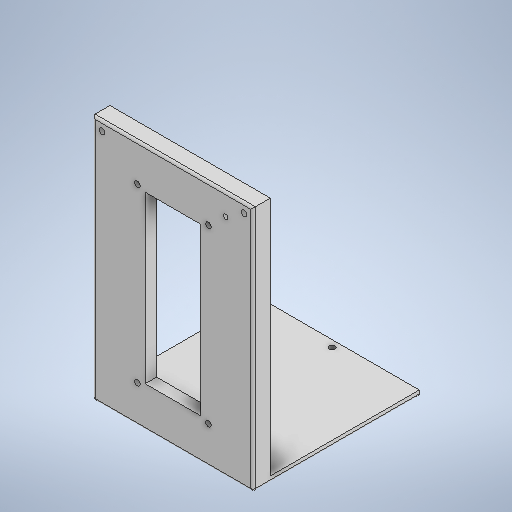
# Autodesk Inventor part: gora
Saved by Autodesk Inventor 2025.2 (Build 292293000, 293)
## iProperties
Created: 2026-10-25
Part Number: gora
Material: Generic
Document SubType Name: Modeling
Designer: Kacper
Density: 1 g/cm^3
Appearance: Default
Author: Kacper
Autodesk Inventor part; units mm, degrees
ref_plane "YZ Plane" through (0, 0, 0) normal (1, 0, 0) x (0, 1, 0)
ref_plane "XZ Plane" through (0, 0, 0) normal (0, 1, 0) x (-1, 0, 0)
ref_plane "XY Plane" through (0, 0, 0) normal (0, 0, 1) x (1, 0, 0)
sketch "Sketch1" plane through (0, 0, 0) normal (0, 0, 1) x (1, 0, 0)
  line L0 (-35, 53.75) -> (35, 53.75)
  line L1 (35, 53.75) -> (35, -53.75)
  line L2 (35, -53.75) -> (-35, -53.75)
  line L3 (-35, -53.75) -> (-35, 53.75)
  line L4 (-35, 53.75) -> (35, -53.75) construction
  line L5 (35, 53.75) -> (-35, -53.75) construction
  point P0 (0, 0)
  dimension "d0" = 70
  dimension "d1" = 107.5
  constraints: 12 end point, 2 midpoint, 2 parallel, 1 horizontal, 1 perpendicular
  measures "d0" distance of L0.start L0.end
  measures "d1" distance of L0.end L1.end
extrude "Extrusion1" add sketch "Sketch1" along normal blind 5
sketch "Sketch6" plane through (0, 0, 0) normal (0, 0, -1) x (-1, 0, 0)
  line L0 (35, -53.75) -> (-35, -53.75) projected
  line L1 (35, 53.75) -> (35, -53.75) projected
  line L2 (-35, 53.75) -> (35, 53.75) projected
  line L3 (-35, -53.75) -> (-35, 53.75) projected
  line L4 (-32.5, 43.442) -> (32.5, 43.442)
  line L5 (32.5, 43.442) -> (32.5, -53.75)
  line L6 (32.5, -53.75) -> (-32.5, -53.75)
  line L7 (-32.5, -53.75) -> (-32.5, 43.442)
  point P0 (0, 0)
  dimension "d47" = 2.5
  dimension "d48" = 2.5
  dimension "d49" = 10.308
  constraints: 8 end point, 2 parallel, 1 horizontal, 1 perpendicular, 1 point on line
  measures "d47" distance between parallel lines of L3 L7
  measures "d48" distance between parallel lines of L1 L5
  measures "d49" distance between parallel lines of L2 L4
extrude "Extrusion3" add sketch "Sketch6" along normal blind 2.5 contours L0 L5 L4 L7 L3 L2 L1
sketch "Sketch7" plane through (0, 0, 5) normal (0, 0, 1) x (1, 0, 0)
  line L0 (-35, -53.75) -> (35, -53.75) projected
  line L1 (35, -53.75) -> (35, 53.75) projected
  line L2 (35, 53.75) -> (-35, 53.75) projected
  line L3 (-35, 53.75) -> (-35, -53.75) projected
  point P0 (0, 0)
  point P1 (-31, 49.75)
  point P2 (31, 49.75)
  dimension "d52" = 4
  dimension "d53" = 4
  dimension "d54" = 4
  dimension "d55" = 4
  measures "d52" distance from line of L2 point (31, 49.75)
  measures "d53" distance from line of point (31, 49.75) L1
  measures "d54" distance from line of L3 point (-31, 49.75)
  measures "d55" distance from line of L2 point (-31, 49.75)
hole "Hole4" at (-31, 49.75, 5) at (31, 49.75, 5) direction (0, 0, -1) diameter 2.459 depth 7.5 thread size "M3x0.5" class "6H" standard "ISO Metric profile"
fillet "Fillet5" radius 1 4 edges at (35, 0, 5) (0, 53.75, 5) (-35, 0, 5) (0, -53.75, 5)
sketch "Sketch8" plane through (0, 0, 0) normal (0, 0, -1) x (-1, 0, 0)
  line L0 (-32.5, 43.442) -> (-32.5, -53.75) projected
  line L1 (32.5, -53.75) -> (-32.5, -53.75) projected
  line L2 (32.5, -53.75) -> (32.5, 43.442) projected
  line L3 (32.5, 43.442) -> (-32.5, 43.442) projected
  line L4 (32.5, -53.75) -> (-32.5, -53.75)
  line L5 (-32.5, -53.75) -> (-32.5, -51.25)
  line L6 (-32.5, -51.25) -> (32.5, -51.25)
  line L7 (32.5, -51.25) -> (32.5, -53.75)
  point P0 (0, 0)
  dimension "d64" = 2.5
  constraints: 8 end point, 2 parallel, 1 horizontal, 1 perpendicular, 1 point on line
  measures "d64" distance between parallel lines of L1 L6
extrude "Extrusion4" add sketch "Sketch8" along normal blind 67.5 contours L6 L2 L1 L0
sketch "Sketch9" plane through (0, 0, -2.5) normal (0, 0, -1) x (-1, 0, 0)
  line L0 (35, -53.75) -> (35, 53.75) projected
  line L1 (32.5, -53.75) -> (35, -53.75) projected
  line L2 (32.5, -53.75) -> (32.5, -51.25) projected
  line L3 (32.5, 43.442) -> (32.5, -51.25) projected
  line L4 (-35, 53.75) -> (-35, -53.75) projected
  line L5 (-35, -53.75) -> (-32.5, -53.75) projected
  line L6 (-32.5, -51.25) -> (-32.5, 43.442) projected
  line L7 (32.5, -51.25) -> (-32.5, -51.25) projected
  line L8 (-32.5, -53.75) -> (32.5, -53.75) projected
  line L9 (-32.5, -51.25) -> (-32.5, -53.75) projected
  line L10 (32.5, -51.25) -> (35, -51.25)
  line L11 (35, -51.25) -> (35, -53.75)
  line L12 (35, -53.75) -> (32.5, -53.75)
  line L13 (32.5, -53.75) -> (32.5, -51.25)
  line L14 (-32.5, -51.25) -> (-35, -51.25)
  line L15 (-35, -51.25) -> (-35, -53.75)
  line L16 (-35, -53.75) -> (-32.5, -53.75)
  line L17 (-32.5, -53.75) -> (-32.5, -51.25)
  point P0 (0, 0)
  constraints: 16 end point, 4 parallel, 2 horizontal, 2 perpendicular
extrude "Extrusion5" add sketch "Sketch9" along normal up to surface (65 mm away) contours L1 L2 L10 L0 | L5 L4 L14 L9
sketch "Sketch11" plane through (-35, -53.75, 4) normal (0, -1, 0) x (1, 0, 0)
  line L0 (0, 0) -> (70, 0) projected
  line L1 (0, 0) -> (0, -71.5) projected
  line L2 (0, -71.5) -> (70, -71.5) projected
  line L3 (70, -71.5) -> (70, 0) projected
  point P0 (35, -4)
  point P1 (35, -68.5)
  dimension "d79" = 3
  dimension "d80" = 35
  measures "d79" distance from line of point (35, -68.5) L2
  measures "d80" distance from line of L3 point (35, -68.5)
hole "Hole6" at (0, -53.75, -64.5) direction (0, 1, 0) diameter 2.459 depth 2.5 thread size "M3x0.5" class "6H" standard "ISO Metric profile"
fillet "Fillet7" radius 1 5 edges at (34.7071, -53.4571, 4.7071) (35, -53.75, -31.75) (-34.7071, -53.4571, 4.7071) (-35, -53.75, -31.75) (0, -53.75, -67.5)
sketch "Sketch12" plane through (0, 0, 5) normal (0, 0, 1) x (1, 0, 0)
  circle A0 centre (-31, 49.75) radius 1.2295 projected
  circle A1 centre (31, 49.75) radius 1.2295 projected
  line L0 (-34, -52.75) -> (-34, 52.75) projected
  line L1 (34, -52.75) -> (-34, -52.75) projected
  line L2 (34, 52.75) -> (34, -52.75) projected
  line L3 (-34, 52.75) -> (34, 52.75) projected
  line L4 (35, -52.75) -> (35, 53.75) projected
  line L5 (-35, 53.75) -> (-35, -52.75) projected
  line L6 (35, 53.75) -> (-35, 53.75) projected
  line L7 (-34, -53.75) -> (34, -53.75) projected
  line L8 (-12.1, 36.2) -> (12.1, 36.2)
  line L9 (12.1, 36.2) -> (12.1, -36.2)
  line L10 (12.1, -36.2) -> (-12.1, -36.2)
  line L11 (-12.1, -36.2) -> (-12.1, 36.2)
  point P0 (0, 0)
  point P1 (-15.5, 37.5)
  point P2 (15.5, 37.5)
  point P3 (-15.5, -37.5)
  point P4 (15.5, -37.5)
  point P5 (0, -36.2)
  point P6 (0, 36.2)
  dimension "d89" = 72.4
  dimension "d90" = 24.2
  dimension "d91" = 21.9
  dimension "d93" = 16.55
  dimension "d95" = 31
  dimension "d96" = 31
  dimension "d97" = 15.5
  dimension "d99" = 15.5
  dimension "d100" = 15.5
  dimension "d101" = 15.5
  dimension "d102" = 75
  dimension "d105" = 1.3
  constraints: 8 end point, 2 midpoint, 2 parallel, 1 horizontal, 1 perpendicular
  measures "d89" distance between parallel lines of L10 L8
  measures "d90" distance between parallel lines of L9 L11
  measures "d91" distance between parallel lines of L11 L0
  measures "d93" distance between parallel lines of L10 L1
  measures "d95" distance of point (15.5, 37.5) point (-15.5, 37.5)
  measures "d96" distance of point (15.5, -37.5) point (-15.5, -37.5)
  measures "d97" horizontal distance of point (0, -36.2) point (15.5, -37.5)
  measures "d99" horizontal distance of point (0, -36.2) point (-15.5, -37.5)
  measures "d100" horizontal distance of point (0, 36.2) point (15.5, 37.5)
  measures "d101" horizontal distance of point (-15.5, 37.5) point (0, 36.2)
  measures "d102" distance of point (-15.5, -37.5) point (-15.5, 37.5)
  measures "d105" distance from line of L10 point (-15.5, -37.5)
hole "Hole7" at (-15.5, 37.5, 5) at (15.5, 37.5, 5) at (-15.5, -37.5, 5) at (15.5, -37.5, 5) direction (0, 0, -1) diameter 2.459 depth 5 thread size "M3x0.5" class "6H" standard "ISO Metric profile"
sketch "Sketch13" plane through (0, 0, 5) normal (0, 0, 1) x (1, 0, 0)
  circle A0 centre (15.5, -37.5) radius 1.2295 projected
  circle A1 centre (-15.5, -37.5) radius 1.2295 projected
  circle A2 centre (15.5, 37.5) radius 1.2295 projected
  circle A3 centre (-15.5, 37.5) radius 1.2295 projected
  circle A4 centre (-31, 49.75) radius 1.2295 projected
  circle A5 centre (31, 49.75) radius 1.2295 projected
  line L0 (-34, -52.75) -> (-34, 52.75) projected
  line L1 (34, -52.75) -> (-34, -52.75) projected
  line L2 (34, 52.75) -> (34, -52.75) projected
  line L3 (-34, 52.75) -> (34, 52.75) projected
  line L4 (-12.1, -36.2) -> (12.1, -36.2)
  line L5 (12.1, -36.2) -> (12.1, 36.2)
  line L6 (12.1, 36.2) -> (-12.1, 36.2)
  line L7 (-12.1, 36.2) -> (-12.1, -36.2)
  point P0 (0, 0)
  dimension "d114" = 72.4
  dimension "d115" = 24.2
  dimension "d117" = 1.3
  dimension "d118" = 3.4
  constraints: 8 end point, 2 parallel, 1 horizontal, 1 perpendicular
  measures "d114" distance between parallel lines of L6 L4
  measures "d115" distance between parallel lines of L5 L7
  measures "d117" distance from line of L6 A2.centre
  measures "d118" distance from line of A1.centre L7
extrude "Extrusion6" cut sketch "Sketch13" against normal up to surface (5 mm away) contours L7 L6 L5 L4
sketch "Sketch14" plane through (0, 0, 5) normal (0, 0, 1) x (1, 0, 0)
  line L0 (12.1, 36.2) -> (12.1, -36.2) projected
  line L1 (12.1, -36.2) -> (-12.1, -36.2) projected
  line L2 (-12.1, -36.2) -> (-12.1, 36.2) projected
  line L3 (-12.1, 36.2) -> (12.1, 36.2) projected
  circle A0 centre (15.5, -37.5) radius 1.2295 projected
  circle A1 centre (-15.5, -37.5) radius 1.2295 projected
  circle A2 centre (15.5, 37.5) radius 1.2295 projected
  circle A3 centre (-15.5, 37.5) radius 1.2295 projected
  circle A4 centre (-31, 49.75) radius 1.2295 projected
  circle A5 centre (31, 49.75) radius 1.2295 projected
  line L4 (-34, -52.75) -> (-34, 52.75) projected
  line L5 (34, -52.75) -> (-34, -52.75) projected
  line L6 (34, 52.75) -> (34, -52.75) projected
  line L7 (-34, 52.75) -> (34, 52.75) projected
  point P0 (0, 0)
  point P1 (23.05, 44.475)
  dimension "d121" = 10.95
  dimension "d122" = 8.275
  measures "d121" distance from line of L6 point (23.05, 44.475)
  measures "d122" distance from line of L7 point (23.05, 44.475)
hole "Hole8" at (23.05, 44.475, 5) direction (0, 0, -1) diameter 2 depth 5
body "Solid1"
